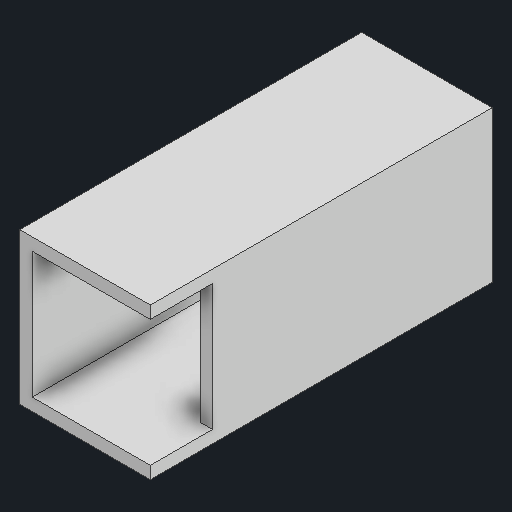
# Autodesk Inventor part: EjeY
Saved by Autodesk Inventor 2027 (Build 310192060, 192F)
## iProperties
Created: 2026-09-12
Part Number: EjeY
Material: Genérico
Document SubType Name: Modeling
Designer: alexa
Density: 1 g/cm^3
Appearance: Valor por defecto
Author: alexa
Autodesk Inventor part; units mm, degrees
ref_plane "YZ Plane" through (0, 0, 0) normal (1, 0, 0) x (0, 1, 0)
ref_plane "XZ Plane" through (0, 0, 0) normal (0, 1, 0) x (-1, 0, 0)
ref_plane "XY Plane" through (0, 0, 0) normal (0, 0, 1) x (1, 0, 0)
sketch "Boceto1" plane through (0, 0, 0) normal (0, 0, 1) x (1, 0, 0)
  line L0 (-5.1, 6.1) -> (5.1, 6.1)
  line L1 (5.1, 6.1) -> (5.1, -6.1)
  line L2 (5.1, -6.1) -> (-5.1, -6.1)
  line L3 (-5.1, -6.1) -> (-5.1, 6.1)
  line L4 (-6.3, 7.3) -> (6.3, 7.3)
  line L5 (6.3, 7.3) -> (6.3, -7.3)
  line L6 (6.3, -7.3) -> (-6.3, -7.3)
  line L7 (-6.3, -7.3) -> (-6.3, 7.3)
  point P0 (0, 0)
  point P1 (-5.1, 0)
  point P2 (0, -6.1)
  point P3 (-5, 0)
  point P4 (0, 6)
  dimension "d0" = 10.2
  dimension "d1" = 12.2
  dimension "d12" = 1.2
  constraints: 16 end point, 4 parallel, 2 horizontal alignment, 2 midpoint, 2 perpendicular, 2 vertical alignment, 1 horizontal, 3 other
  measures "d0" distance of L0.start L0.end
  measures "d1" distance of L2.end L0.start
  measures "d12" distance between parallel lines of L3 L7
extrude "Extrusión2" add sketch "Boceto1" along normal blind 25
sketch "Boceto2" plane through (0, 0, 0) normal (0, 0, -1) x (-1, 0, 0)
  line L0 (6.3, -7.3) -> (-6.3, -7.3) projected
  line L1 (6.3, 7.3) -> (6.3, -7.3) projected
  line L2 (-6.3, 7.3) -> (6.3, 7.3) projected
  line L3 (-6.3, -7.3) -> (-6.3, 7.3) projected
  line L4 (5.1, 6.1) -> (-5.1, 6.1) projected
  line L5 (5.1, -6.1) -> (5.1, 6.1) projected
  line L6 (-5.1, -6.1) -> (5.1, -6.1) projected
  line L7 (-5.1, 6.1) -> (-5.1, -6.1) projected
  spline S0 degree 3 poles (-1.25, 0.05) (-1.2518, 0.3901) (-0.9687, 1.0691) (0.0497, 1.4916) (1.0695, 1.0693) (1.4913, 0.05) (1.1937, -0.6693) (0.9123, -0.9247) (0.8816, -0.95) knots 0 0 0 0 1.020992 2.041984 3.062975 4.083967 5.104959 5.224449 5.224449 5.224449 5.224449 projected
  spline S1 degree 3 poles (-0.7813, -0.95) (-0.812, -0.9247) (-1.0937, -0.6694) (-1.2518, -0.2901) (-1.25, 0.05) knots 7.027356 7.027356 7.027356 7.027356 7.146943 8.167935 8.167935 8.167935 8.167935 projected
  line L8 (0.8816, -0.95) -> (-0.7813, -0.95) projected
  line L9 (-0.8891, -1.25) -> (0.9894, -1.25)
  line L10 (0, 0) -> (0.0508, 4.5497)
  line L11 (0, 0) -> (0.0501, -4.4676)
  circle A0 centre (0.0501, -4.4676) radius 0.8
  line L12 (0, 0) -> (0, -3)
  circle A1 centre (0.0508, 4.5497) radius 0.8
  line L13 (0, 0) -> (0, 3)
  spline S2 degree 3 poles (2.2501, 0.05) (2.2501, 0.3379) (2.1355, 0.9138) (1.6462, 1.6462) (0.9139, 2.1355) (0.05, 2.3073) (-0.8138, 2.1355) (-1.5462, 1.6462) (-2.0355, 0.9138) (-2.1502, 0.338) (-2.15, 0.05) knots 6.911329 6.911329 6.911329 6.911329 7.775245 8.639162 9.503078 10.366994 11.23091 12.094826 12.958742 13.822658 13.822658 13.822658 13.822658 weights 1 1 1 1 1 1 1 1 1 1 1 projected
  spline S3 degree 3 poles (-2.15, 0.05) (-2.1502, -0.2379) (-2.0355, -0.8138) (-1.5462, -1.5462) (-0.8138, -2.0355) (0.05, -2.2073) (0.9138, -2.0355) (1.6462, -1.5462) (2.1355, -0.8139) (2.2501, -0.238) (2.2501, 0.05) knots 0 0 0 0 0.863916 1.727832 2.591748 3.455665 4.319581 5.183497 6.047413 6.911329 6.911329 6.911329 6.911329 weights 1 1 1 1 1 1 1 1 1 1 1 projected
  point P0 (-1.55, 0.05)
  dimension "d13" = 0.3
  dimension "d14" = 4.55
  dimension "d16" = 1.6
  dimension "d17" = 3
  dimension "d18" = 0.643
  dimension "d19" = 4.4676
  dimension "d20" = 1.6
  dimension "d21" = 3
  dimension "d22" = 0.64
  constraints: 10 end point, 2 centre point, 2 coincident, 2 vertical, 1 parallel, 6 other
  measures "d14" distance of L10.start L10.end
  measures "d16" diameter of A0
  measures "d17" distance of L10.start L12.end
  measures "d18" angle of L12 L11
  measures "d19" vertical distance of L10.start L11.end
  measures "d20" diameter of A1
  measures "d21" distance of L10.start L13.end
  measures "d22" angle of L10 L13
extrude "Extrusión3" add sketch "Boceto2" along normal blind 2 contours L0 L3 L2 L1 | L5 L6 L7 L4
sketch "Boceto3" plane through (0, 0, 25) normal (0, 0, 1) x (1, 0, 0)
  line L0 (-6.3, -7.3) -> (6.3, -7.3) projected
  line L1 (6.3, -7.3) -> (6.3, 7.3) projected
  line L2 (6.3, 7.3) -> (-6.3, 7.3) projected
  line L3 (-6.3, 7.3) -> (-6.3, -7.3) projected
  line L4 (-5.1, 6.1) -> (5.1, 6.1) projected
  line L5 (5.1, 6.1) -> (5.1, -6.1) projected
  line L6 (5.1, -6.1) -> (-5.1, -6.1) projected
  line L7 (-5.1, -6.1) -> (-5.1, 6.1) projected
  line L8 (5.1, 6.1) -> (6.3, 6.1)
  line L9 (-5.1, -6.1) -> (-5.1, 6.1) projected
  line L10 (-5.1, 6.1) -> (-6.3, 6.1)
  line L11 (5.1, 6.1) -> (5.1, -6.1) projected
  line L12 (5.1, -6.1) -> (6.3, -6.1)
  line L13 (-5.1, -6.1) -> (-6.3, -6.1)
  point P0 (0, 0)
  constraints: 8 end point, 6 point on line, 2 perpendicular
extrude "Extrusión4" add sketch "Boceto3" along normal blind 6 contours L3 L13 L6 L12 L1 L0 | L3 L10 L7 L13 | L3 L2 L1 L8 L4 L10
